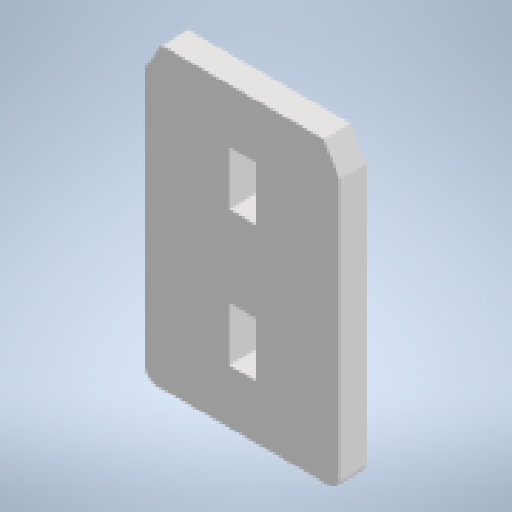
# Autodesk Inventor part: StandTop
Saved by Autodesk Inventor 2025.2 (Build 292293000, 293)
## iProperties
Created: 2025-07-03
Part Number: StandTop
Material: Generic
Document SubType Name: Modeling
Designer: ricoa
Density: 1 g/cm^3
Appearance: Default
Author: ricoa
Autodesk Inventor part; units mm, degrees
ref_plane "YZ Plane" through (0, 0, 0) normal (1, 0, 0) x (0, 1, 0)
ref_plane "XZ Plane" through (0, 0, 0) normal (0, 1, 0) x (-1, 0, 0)
ref_plane "XY Plane" through (0, 0, 0) normal (0, 0, 1) x (1, 0, 0)
sketch "Sketch1" plane through (0, 0, 0) normal (0, 0, 1) x (1, 0, 0)
  circle A0 centre (40, 23.75) radius 1.25 projected
  circle A1 centre (-36, -28.75) radius 1.25 projected
  circle A2 centre (36, -28.75) radius 1.25 projected
  circle A3 centre (-40, 23.75) radius 1.25 projected
  circle A4 centre (45, 23.75) radius 1.25 projected
  circle A5 centre (-46, -28.75) radius 1.25 projected
  circle A6 centre (46, -28.75) radius 1.25 projected
  circle A7 centre (-45, 23.75) radius 1.25 projected
  line L0 (-57, -3.75) -> (-62, -3.75) projected
  line L1 (-62, -3.75) -> (-62, -13.75) projected
  line L2 (-62, -13.75) -> (-57, -13.75) projected
  line L3 (-57, -13.75) -> (-57, -23.75) projected
  line L4 (-57, -23.75) -> (-62, -23.75) projected
  line L5 (-62, -23.75) -> (-62, -33.75) projected
  line L6 (-62, -33.75) -> (62, -33.75) projected
  line L7 (62, -33.75) -> (62, -23.75) projected
  line L8 (62, -23.75) -> (57, -23.75) projected
  line L9 (57, -23.75) -> (57, -13.75) projected
  line L10 (57, -13.75) -> (62, -13.75) projected
  line L11 (62, -13.75) -> (62, -3.75) projected
  line L12 (62, -3.75) -> (57, -3.75) projected
  line L13 (57, -3.75) -> (57, 3.75) projected
  line L14 (57, 3.75) -> (62, 3.75) projected
  line L15 (62, 3.75) -> (62, 13.75) projected
  line L16 (62, 13.75) -> (57, 13.75) projected
  line L17 (57, 13.75) -> (57, 23.75) projected
  line L18 (57, 23.75) -> (62, 23.75) projected
  line L19 (62, 23.75) -> (62, 33.75) projected
  line L20 (62, 33.75) -> (52, 33.75) projected
  line L21 (52, 33.75) -> (52, 28.75) projected
  line L22 (52, 28.75) -> (42, 28.75) projected
  line L23 (42, 28.75) -> (42, 33.75) projected
  line L24 (42, 33.75) -> (32, 33.75) projected
  line L25 (32, 33.75) -> (32, 28.75) projected
  line L26 (32, 28.75) -> (22, 28.75) projected
  line L27 (22, 28.75) -> (22, 33.75) projected
  line L28 (22, 33.75) -> (12, 33.75) projected
  line L29 (12, 33.75) -> (12, 28.75) projected
  line L30 (12, 28.75) -> (2, 28.75) projected
  line L31 (2, 28.75) -> (2, 33.75) projected
  line L32 (2, 33.75) -> (-2, 33.75) projected
  line L33 (-2, 33.75) -> (-2, 28.75) projected
  line L34 (-2, 28.75) -> (-12, 28.75) projected
  line L35 (-12, 28.75) -> (-12, 33.75) projected
  line L36 (-12, 33.75) -> (-22, 33.75) projected
  line L37 (-22, 33.75) -> (-22, 28.75) projected
  line L38 (-22, 28.75) -> (-32, 28.75) projected
  line L39 (-32, 28.75) -> (-32, 33.75) projected
  line L40 (-32, 33.75) -> (-42, 33.75) projected
  line L41 (-42, 33.75) -> (-42, 28.75) projected
  line L42 (-42, 28.75) -> (-52, 28.75) projected
  line L43 (-52, 28.75) -> (-52, 33.75) projected
  line L44 (-52, 33.75) -> (-62, 33.75) projected
  line L45 (-62, 33.75) -> (-62, 23.75) projected
  line L46 (-62, 23.75) -> (-57, 23.75) projected
  line L47 (-57, 23.75) -> (-57, 13.75) projected
  line L48 (-57, 13.75) -> (-62, 13.75) projected
  line L49 (-62, 13.75) -> (-62, 3.75) projected
  line L50 (-62, 3.75) -> (-57, 3.75) projected
  line L51 (-57, 3.75) -> (-57, -3.75) projected
  circle A8 centre (-37.5, 9.5) radius 10 projected
  circle A9 centre (-48.5, -22.5) radius 1.25 projected
  circle A10 centre (48.5, 17.5) radius 1.25 projected
  circle A11 centre (-26.5, -22.5) radius 1.25 projected
  circle A12 centre (48.5, -22.5) radius 1.25 projected
  circle A13 centre (-48.5, 17.5) radius 1.25 projected
  circle A14 centre (26.5, 17.5) radius 1.25 projected
  circle A15 centre (37.5, 9.5) radius 10 projected
  circle A16 centre (-26.5, 17.5) radius 1.25 projected
  circle A17 centre (26.5, -22.5) radius 1.25 projected
  line L52 (-51.75, 18.75) -> (-51.75, -23.75) projected
  line L53 (-49.75, 20.75) -> (-51.75, 18.75) projected
  line L54 (-49.75, 20.75) -> (-25.25, 20.75) projected
  line L55 (-23.25, 18.75) -> (-25.25, 20.75) projected
  line L56 (-23.25, 18.75) -> (-23.25, -23.75) projected
  line L57 (-25.25, -25.75) -> (-23.25, -23.75) projected
  line L58 (-49.75, -25.75) -> (-25.25, -25.75) projected
  line L59 (-51.75, -23.75) -> (-49.75, -25.75) projected
  circle A18 centre (37.5, 9.5) radius 1 projected
  line L60 (49.6464, 20.5) -> (25.3536, 20.5) projected
  line L61 (25.3536, 20.5) -> (23.5, 18.6464) projected
  line L62 (23.5, 18.6464) -> (23.5, -23.6464) projected
  line L63 (23.5, -23.6464) -> (25.3536, -25.5) projected
  line L64 (25.3536, -25.5) -> (49.6464, -25.5) projected
  line L65 (49.6464, -25.5) -> (51.5, -23.6464) projected
  line L66 (51.5, -23.6464) -> (51.5, 18.6464) projected
  line L67 (51.5, 18.6464) -> (49.6464, 20.5) projected
  line L68 (42.75, -15.75) -> (32.25, -15.75) projected
  arc A19 (44.25, -17.25) -> (42.75, -15.75) centre (42.75, -17.25) ccw projected
  line L69 (44.25, -22.25) -> (44.25, -17.25) projected
  arc A20 (42.75, -23.75) -> (44.25, -22.25) centre (42.75, -22.25) ccw projected
  line L70 (32.25, -23.75) -> (42.75, -23.75) projected
  arc A21 (30.75, -22.25) -> (32.25, -23.75) centre (32.25, -22.25) ccw projected
  line L71 (30.75, -17.25) -> (30.75, -22.25) projected
  arc A22 (32.25, -15.75) -> (30.75, -17.25) centre (32.25, -17.25) ccw projected
  circle A23 centre (48.5, -22.5) radius 2.5 projected
  circle A24 centre (26.5, 17.5) radius 2.5 projected
  circle A25 centre (48.5, 1.5) radius 1 projected
  circle A26 centre (26.5, 1.5) radius 1 projected
  circle A27 centre (48.5, 17.5) radius 2.5 projected
  circle A28 centre (26.5, -22.5) radius 2.5 projected
  line L72 (20, -30.75) -> (20, -33.75) projected
  line L73 (-20, -33.75) -> (-20, -30.75) projected
  line L74 (15, 28.25) -> (-15, 28.25) projected
  line L75 (15, 25) -> (-15, 25)
  line L76 (15, 25) -> (-15, -25) construction
  line L77 (-15, 25) -> (15, -25) construction
  line L78 (0, 0) -> (0, -30)
  line L79 (0, 0) -> (30, 0) construction
  line L80 (0, -30) -> (18, -30)
  line L81 (18, -30) -> (18, 20)
  line L82 (18, 20) -> (15, 25)
  line L83 (0, -30) -> (-18, -30)
  line L84 (-18, -30) -> (-18, 20)
  line L85 (-18, 20) -> (-15, 25)
  dimension "d2" = 30
  dimension "d3" = 90
  dimension "d4" = 18
  dimension "d5" = 18
  constraints: 22 end point, 2 horizontal, 2 midpoint, 2 perpendicular, 2 vertical, 1 point on line
  measures "d2" distance of L78.start L78.end
  measures "d3" angle of L78 L79
  measures "d4" distance of L78.end L80.end
  measures "d5" distance of L78.end L83.end
extrude "Extrusion1" add sketch "Sketch1" along normal blind 5 contours L82 L81 L80 L83 L84 L85 L75
sketch "Sketch2" plane through (0, 0, 0) normal (0, 0, -1) x (-1, 0, 0)
  line L0 (-15, 25) -> (15, 25) projected
  line L1 (-2.5, -25) -> (-2.5, 25)
  line L2 (-2.5, 25) -> (2.5, 25)
  line L3 (2.5, 25) -> (2.5, -25)
  line L4 (2.5, -25) -> (-2.5, 25) construction
  line L5 (-2.5, -25) -> (2.5, 25) construction
  line L6 (2.5, -25) -> (2.5, -30)
  line L7 (18, -30) -> (-18, -30) projected
  line L8 (-2.5, -25) -> (-2.5, -30)
  line L9 (-2.5, 25) -> (-2.5, 15)
  line L10 (-2.5, 15) -> (2.5, 15)
  line L11 (-2.5, 15) -> (-2.5, 5)
  line L12 (-2.5, 5) -> (2.5, 5)
  line L13 (-2.5, -30) -> (-2.5, -20)
  line L14 (-2.5, -20) -> (2.5, -20)
  line L15 (2.5, -20) -> (2.5, -10)
  line L16 (2.5, -10) -> (-2.5, -10)
  point P0 (0, 0)
  dimension "d6" = 5
  dimension "d7" = 10
  dimension "d8" = 10
  dimension "d10" = 10
  dimension "d11" = 10
  constraints: 30 end point, 11 point on line, 4 perpendicular, 2 midpoint, 2 parallel, 1 vertical
  measures "d6" distance of L1.end L2.end
  measures "d7" distance of L1.end L9.end
  measures "d8" distance of L9.end L11.end
  measures "d10" distance of L8.end L13.end
  measures "d11" distance of L14.end L15.end
extrude "Extrusion2" cut sketch "Sketch2" against normal blind 5 contours L10 L3 L12 L1 | L16 L3 L14 L1
fillet "Fillet1" radius 2 2 edges at (-18, -30, 2.5) (18, -30, 2.5)
body "Solid1"
